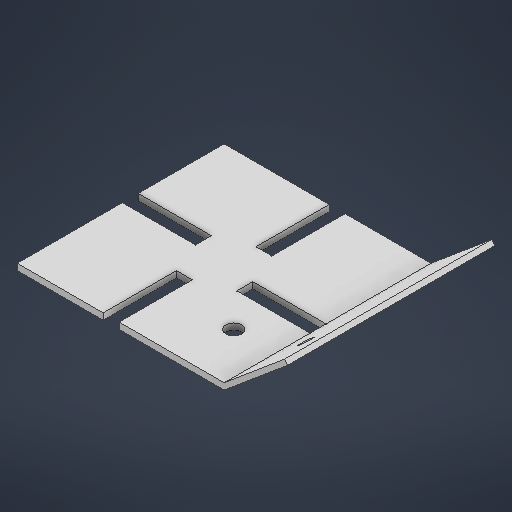
# Autodesk Inventor part: dziurynaczujnik
Saved by Autodesk Inventor 2026.1 (Build 301233020, 233B)
## iProperties
Created: 2026-09-17
Part Number: dziurynaczujnik
Material: Ogólny
Document SubType Name: Modeling
Designer: Bronh
Density: 1 g/cm^3
Appearance: Domyślna
Author: Bronh
Autodesk Inventor part; units mm, degrees
ref_plane "YZ Plane" through (0, 0, 0) normal (1, 0, 0) x (0, 1, 0)
ref_plane "XZ Plane" through (0, 0, 0) normal (0, 1, 0) x (-1, 0, 0)
ref_plane "XY Plane" through (0, 0, 0) normal (0, 0, 1) x (1, 0, 0)
sketch "Szkic2" plane through (-85, -17.9556, 0) normal (0, 0, 1) x (1, 0, 0)
  line L0 (0, 0) -> (130, 0)
  line L1 (130, 0) -> (170, 33.564)
  line L2 (0, 0) -> (0, 4)
  line L3 (0, 4) -> (130, 4)
  line L4 (130, 4) -> (168.0304, 35.9113)
  line L5 (168.0304, 35.9113) -> (170, 33.564)
  dimension "d7" = 130
  dimension "d6" = 40
  dimension "d5" = 4
  dimension "d4" = 130
  dimension "d2" = 90
  dimension "d3" = 38.0304
  constraints: 12 end point, 2 perpendicular, 1 horizontal, 1 vertical
  measures "d7" distance of L0.start L0.end
  measures "d6" horizontal distance of L0.end L1.end
  measures "d5" distance of L0.start L2.end
  measures "d4" distance of L2.end L3.end
  measures "d2" angle of L5 L1
  measures "d3" horizontal distance of L3.end L4.end
extrude "Wyciągnięcie proste1" add sketch "Szkic2" along normal blind 130
sketch "Szkic3" plane through (45, -13.9556, 130) normal (-0.6427876, 0.7660444, 0) x (0.7660444, 0.6427876, 0)
  line L0 (49.6451, 130) -> (49.6451, 0) projected
  line L1 (49.6451, 0) -> (0, 0) projected
  point P0 (-25.5015, 130)
  point P1 (26.2741, 31.25)
  dimension "d11" = 23.371
  dimension "d12" = 31.25
  measures "d11" distance from line of point (26.274, 31.25) L0
  measures "d12" distance from line of L1 point (26.274, 31.25)
hole "Otwór1" at (65.1272, 2.9331, 98.75) direction (0.6427876, -0.7660444, 0) diameter 8.5 depth 4
sketch "Szkic5" plane through (-85, -13.9556, 0) normal (0, 1, 0) x (1, 0, 0)
  line L0 (130, 0) -> (0, 0) projected
  line L1 (76, 0) -> (66, 0)
  line L2 (66, 0) -> (66, -46)
  line L3 (66, -46) -> (76, -46)
  line L4 (76, -46) -> (76, 0)
  line L5 (0, 0) -> (0, -130) projected
  point P0 (85, 0)
  dimension "d30" = 46
  dimension "d76" = 10
  dimension "d77" = 66
  constraints: 8 end point, 2 parallel, 1 horizontal, 1 perpendicular, 1 point on line
  measures "d30" distance of L3.end L1.start
  measures "d76" distance of L2.end L3.end
  measures "d77" distance between parallel lines of L5 L2
extrude "Wyciągnięcie proste2" cut sketch "Szkic5" against normal blind 10
sketch "Szkic6" plane through (-85, -13.9556, 130) normal (0, 1, 0) x (1, 0, 0)
  line L0 (130, 0) -> (0, 0) projected
  line L1 (64, 46) -> (54, 46)
  line L2 (54, 46) -> (54, 0)
  line L3 (54, 0) -> (64, 0)
  line L4 (64, 0) -> (64, 46)
  line L5 (0, 130) -> (0, 0) projected
  point P0 (85, 130)
  dimension "d33" = 46
  dimension "d34" = 10
  dimension "d35" = 54
  constraints: 8 end point, 2 parallel, 1 horizontal, 1 perpendicular, 1 point on line
  measures "d33" distance of L3.end L1.start
  measures "d34" distance of L1.start L1.end
  measures "d35" distance between parallel lines of L5 L2
extrude "Wyciągnięcie proste3" cut sketch "Szkic6" against normal blind 10
sketch "Szkic7" plane through (45, -13.9556, 130) normal (0, 1, 0) x (1, 0, 0)
  line L0 (0, 130) -> (0, 0) projected
  line L1 (0, 64) -> (-46, 64)
  line L2 (-46, 64) -> (-46, 54)
  line L3 (-46, 54) -> (0, 54)
  line L4 (0, 54) -> (0, 64)
  line L5 (0, 0) -> (-66, 0) projected
  point P0 (-45, 130)
  point P1 (0, 54)
  dimension "d38" = 46
  dimension "d40" = 54
  dimension "d75" = 10
  constraints: 8 end point, 2 parallel, 1 horizontal, 1 perpendicular, 1 point on line
  measures "d38" distance of L3.end L2.end
  measures "d40" distance between parallel lines of L5 L3
  measures "d75" distance of L1.end L2.end
extrude "Wyciągnięcie proste4" cut sketch "Szkic7" against normal blind 10
sketch "Szkic9" plane through (-85, -13.9556, 130) normal (0, 1, 0) x (1, 0, 0)
  line L0 (0, 130) -> (0, 0) projected
  line L1 (46, 76) -> (0, 76)
  line L2 (0, 76) -> (0, 66)
  line L3 (0, 66) -> (46, 66)
  line L4 (46, 66) -> (46, 76)
  line L5 (54, 0) -> (0, 0) projected
  line L6 (66, 130) -> (0, 130) projected
  point P0 (85, 130)
  point P1 (0, 76)
  dimension "d43" = 10
  dimension "d44" = 46
  dimension "d78" = 54
  constraints: 8 end point, 2 parallel, 1 horizontal, 1 perpendicular, 1 point on line
  measures "d43" distance of L3.end L1.start
  measures "d44" distance of L2.end L3.end
  measures "d78" distance between parallel lines of L6 L1
extrude "Wyciągnięcie proste5" cut sketch "Szkic9" against normal blind 10
sketch "Szkic10" plane through (-9, -13.9556, 0) normal (0, 1, 0) x (1, 0, 0)
  line L0 (-22, -130) -> (-22, -84) projected
  line L1 (-22, -130) -> (-76, -130) projected
  line L2 (-12, -84) -> (-12, -130) projected
  line L3 (54, -130) -> (-12, -130) projected
  line L4 (54, -76) -> (54, -130) projected
  point P0 (9, 0)
  point P1 (28, -98)
  dimension "d74" = 32
  dimension "d79" = 26
  measures "d74" distance from line of L3 point (28, -98)
  measures "d79" distance from line of L4 point (28, -98)
hole "Otwór3" at (19, -13.9556, 98) direction (0, -1, 0) diameter 10 depth 4
